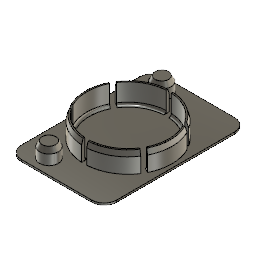
cover_cap (Autodesk Fusion 360 design; units mm, degrees)
Autodesk Fusion 360 part; units mm, degrees
sketch "Sketch1" plane through (0, 0, 0) normal (0, 0, 1) x (1, 0, 0)
  line L0 (14, 28.5) -> (-14, 28.5)
  line L1 (-19, 23.5) -> (-19, -23.5)
  line L2 (-14, -28.5) -> (14, -28.5)
  line L3 (19, -23.5) -> (19, 23.5)
  line L4 (20.6675, 31.0012) -> (-19, -28.5) construction
  line L5 (-19, 28.5) -> (19, -28.5) construction
  arc A0 (-14, 28.5) -> (-19, 23.5) centre (-14, 23.5) ccw
  arc A1 (19, 23.5) -> (14, 28.5) centre (14, 23.5) ccw
  arc A2 (14, -28.5) -> (19, -23.5) centre (14, -23.5) ccw
  arc A3 (-19, -23.5) -> (-14, -28.5) centre (-14, -23.5) ccw
  dimension "d1" = 57
  dimension "d2" = 38
  dimension "d3" = 5
  constraint perpendicular L0 L1
  constraint parallel L0 L2
  constraint parallel L1 L3
  constraint horizontal L0
  constraint coincident L4 origin
  constraint coincident L5 origin
  constraint coincident L5.start L1
  constraint coincident L5.start L0
  constraint tangent L1 A0
  constraint tangent L0 A0
  constraint tangent L0 A1
  constraint tangent L3 A1
  constraint equal A0 A1
  constraint coincident L5.end L3
  constraint coincident L5.end L2
  constraint tangent L3 A2
  constraint tangent L2 A2
  constraint equal A0 A2
  constraint coincident L4.end L2
  constraint coincident L4.end L1
  constraint tangent L2 A3
  constraint tangent L1 A3
  constraint equal A0 A3
  measures "d1" distance of L5.start L4.end
  measures "d2" distance of L4.end L5.end
  measures "d3" radius of A0
extrude "Extrude1" add sketch "Sketch1" along normal blind 0.8
sketch "Sketch2" plane through (0, 0, 0.8) normal (0, 0, 1) x (-1, 0, 0)
  arc A0 (19, 23.5) -> (14, 28.5) centre (14, 23.5) ccw
  line L0 (14, 28.5) -> (-14, 28.5)
  arc A1 (-14, 28.5) -> (-19, 23.5) centre (-14, 23.5) ccw
  line L1 (-19, 23.5) -> (-19, -23.5)
  arc A2 (-19, -23.5) -> (-14, -28.5) centre (-14, -23.5) ccw
  line L2 (-14, -28.5) -> (14, -28.5)
  arc A3 (14, -28.5) -> (19, -23.5) centre (14, -23.5) ccw
  line L3 (19, -23.5) -> (19, 23.5)
  circle A4 centre (0, 0) radius 17.5
  circle A5 centre (0, 0) radius 16.3
  line L4 (-1, 25) -> (1, 25)
  line L5 (1, 25) -> (1, -25)
  line L6 (1, -25) -> (-1, -25)
  line L7 (-1, -25) -> (-1, 25)
  line L8 (-1, 25) -> (1, -25) construction
  line L9 (1, 25) -> (-1, -25) construction
  line L10 (22.1506, 11.634) -> (-21.1506, -13.366)
  line L11 (-22.1506, -11.634) -> (21.1506, 13.366)
  line L12 (-21.1506, 13.366) -> (22.1506, -11.634)
  line L13 (21.1506, -13.366) -> (-22.1506, 11.634)
  circle A6 centre (9, -22.5) radius 3.75
  line L14 (34, 0) -> (-41, 0) construction
  circle A7 centre (9, 22.5) radius 3.75
  dimension "d6" = 35
  dimension "d7" = 1.2
  dimension "d8" = 50
  dimension "d9" = 2
  dimension "d11" = 360
  dimension "d14" = 7.5
  dimension "d21" = 22.5
  dimension "d22" = 10
  constraint coincident A4.centre A5.centre
  constraint perpendicular L4 L5
  constraint parallel L4 L6
  constraint parallel L5 L7
  constraint horizontal L4
  constraint coincident L8 A4.centre
  constraint coincident L9 A4.centre
  constraint horizontal L14
  constraint symmetric A6 L14 A7
  measures "d6" diameter of A4
  measures "d8" distance of L4.end L5.end
  measures "d9" distance of L5.end L6.end
  measures "d14" diameter of A6
  measures "d21" distance of A6.centre L14
  measures "d22" distance of L3 A6.centre
extrude "Extrude2" add sketch "Sketch2" along normal blind 8 contours A4 A5 L5 L11 | A4 A5 L10 L12 | A4 A5 L7 L12 | A4 A5 L5 L13 | A4 A5 L11 L13 | A4 A5 L7 L10
extrude "Extrude3" add sketch "Sketch2" along normal blind 6 contours A6 | A7
chamfer "Chamfer1" distance 1 distance2 2 2 edges at (-5.5038, 23.8561, 6.8) (-5.5038, -21.1439, 6.8) measured on face at (-6.9706, 23.1785, 6.8) measured on face at (-6.9706, -21.8215, 6.8)
chamfer "Chamfer2" distance 0.6 distance2 2 6 edges at (8.75, -15.1554, 8.8) (17.5, 0, 8.8) (8.75, 15.1554, 8.8) (-8.75, 15.1554, 8.8) (-17.5, 0, 8.8) (-8.75, -15.1554, 8.8) measured on face at (13.8152, -10.021, 8.8) measured on face at (15.586, -6.9538, 8.8) measured on face at (13.8152, 10.021, 8.8) measured on face at (-1.7709, 16.9748, 8.8) measured on face at (-15.586, 6.9538, 8.8) measured on face at (-1.7709, -16.9748, 8.8)
fillet "Fillet1" radius 1 6 edges at (-8.15, 14.1162, 0.8) (-16.3, 0, 0.8) (-8.15, -14.1162, 0.8) (8.15, -14.1162, 0.8) (16.3, 0, 0.8) (8.15, 14.1162, 0.8)
equation "d21 = ( 45 / 2 ) * 1 mm"
